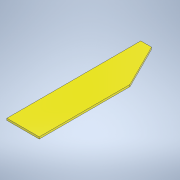
# Autodesk Inventor part: picior_interior_lung
Saved by Autodesk Inventor 2022.6 (Build 266554000, 554)
## iProperties
Created: 2025-04-23
Part Number: picior_interior_lung
Material: Generic
Document SubType Name: Modeling
Designer: Dragos Macovei
Density: 1 g/cm^3
Appearance: Default
Author: Dragos Macovei
Autodesk Inventor part; units mm, degrees
ref_plane "YZ Plane" through (0, 0, 0) normal (1, 0, 0) x (0, 1, 0)
ref_plane "XZ Plane" through (0, 0, 0) normal (0, 1, 0) x (-1, 0, 0)
ref_plane "XY Plane" through (0, 0, 0) normal (0, 0, 1) x (1, 0, 0)
sketch "Sketch1" plane through (0, 0, 0) normal (0, 1, 0) x (-1, 0, 0)
  line L0 (200, 18) -> (300, 18)
  line L1 (300, 18) -> (300, 1260)
  line L2 (300, 1260) -> (0, 1260)
  line L3 (0, 1260) -> (0, 418)
  line L4 (0, 418) -> (200, 18)
  point P0 (0, 0)
  dimension "d0" = 1242
  dimension "d1" = 300
  dimension "d2" = 400
  dimension "d3" = 100
  constraints: 10 end point, 2 parallel, 1 horizontal, 1 perpendicular
  measures "d0" distance of L1.end L0.end
  measures "d1" distance of L1.end L2.end
  measures "d2" distance from line of L3.end L0
  measures "d3" distance from line of L0.start L1
extrude "Extrusion1" add sketch "Sketch1" along normal blind 18
body "Solid1"
